Autodesk Fusion 360 part; units mm, degrees
(part 25 of 28)
  line L2372 (136.268, 61.3167, -1.4859) -> (136.2719, 61.4148, -1.4859)
  line L2373 (136.2719, 61.4148, -1.4859) -> (136.3026, 61.6085, -1.4859)
  line L2374 (136.3026, 61.6085, -1.4859) -> (136.3632, 61.7951, -1.4859)
  line L2375 (136.3632, 61.7951, -1.4859) -> (136.4522, 61.9699, -1.4859)
  line L2376 (136.4522, 61.9699, -1.4859) -> (136.5675, 62.1286, -1.4859)
  line L2377 (136.5675, 62.1286, -1.4859) -> (136.7062, 62.2672, -1.4859)
  line L2378 (136.7062, 62.2672, -1.4859) -> (136.8649, 62.3825, -1.4859)
  line L2379 (136.8649, 62.3825, -1.4859) -> (137.0397, 62.4716, -1.4859)
  line L2380 (137.0397, 62.4716, -1.4859) -> (137.2262, 62.5322, -1.4859)
  line L2381 (137.2262, 62.5322, -1.4859) -> (137.42, 62.5629, -1.4859)
  line L2382 (137.42, 62.5629, -1.4859) -> (137.6161, 62.5629, -1.4859)
  line L2383 (137.6161, 62.5629, -1.4859) -> (137.8099, 62.5322, -1.4859)
  line L2384 (16.561, 65.3929, -1.4859) -> (16.7547, 65.3622, -1.4859)
  line L2385 (16.7547, 65.3622, -1.4859) -> (16.9412, 65.3016, -1.4859)
  line L2386 (16.9412, 65.3016, -1.4859) -> (17.116, 65.2126, -1.4859)
  line L2387 (17.116, 65.2126, -1.4859) -> (17.2747, 65.0973, -1.4859)
  line L2388 (17.2747, 65.0973, -1.4859) -> (17.4134, 64.9586, -1.4859)
  line L2389 (17.4134, 64.9586, -1.4859) -> (17.5287, 64.7999, -1.4859)
  line L2390 (17.5287, 64.7999, -1.4859) -> (17.6177, 64.6251, -1.4859)
  line L2391 (17.6177, 64.6251, -1.4859) -> (17.6784, 64.4386, -1.4859)
  line L2392 (17.6784, 64.4386, -1.4859) -> (17.709, 64.2448, -1.4859)
  line L2393 (17.709, 64.2448, -1.4859) -> (17.709, 64.0487, -1.4859)
  line L2394 (17.709, 64.0487, -1.4859) -> (17.6784, 63.855, -1.4859)
  line L2395 (17.6784, 63.855, -1.4859) -> (17.6177, 63.6684, -1.4859)
  line L2396 (17.6177, 63.6684, -1.4859) -> (17.5287, 63.4936, -1.4859)
  line L2397 (17.5287, 63.4936, -1.4859) -> (17.4134, 63.335, -1.4859)
  line L2398 (17.4134, 63.335, -1.4859) -> (17.2747, 63.1963, -1.4859)
  line L2399 (17.2747, 63.1963, -1.4859) -> (17.116, 63.081, -1.4859)
  line L2400 (17.116, 63.081, -1.4859) -> (16.9412, 62.9919, -1.4859)
  line L2401 (16.9412, 62.9919, -1.4859) -> (16.7547, 62.9313, -1.4859)
  line L2402 (16.7547, 62.9313, -1.4859) -> (16.561, 62.9006, -1.4859)
  line L2403 (16.561, 62.9006, -1.4859) -> (16.4629, 62.8968, -1.4859)
  line L2404 (16.4629, 62.8968, -1.4859) -> (15.9629, 62.8968, -1.4859)
  line L2405 (15.9629, 62.8968, -1.4859) -> (15.8648, 62.9006, -1.4859)
  line L2406 (15.8648, 62.9006, -1.4859) -> (15.6711, 62.9313, -1.4859)
  line L2407 (15.6711, 62.9313, -1.4859) -> (15.4845, 62.9919, -1.4859)
  line L2408 (15.4845, 62.9919, -1.4859) -> (15.3098, 63.081, -1.4859)
  line L2409 (15.3098, 63.081, -1.4859) -> (15.1511, 63.1963, -1.4859)
  line L2410 (15.1511, 63.1963, -1.4859) -> (15.0124, 63.335, -1.4859)
  line L2411 (15.0124, 63.335, -1.4859) -> (14.8971, 63.4936, -1.4859)
  line L2412 (14.8971, 63.4936, -1.4859) -> (14.808, 63.6684, -1.4859)
  line L2413 (14.808, 63.6684, -1.4859) -> (14.7474, 63.855, -1.4859)
  line L2414 (14.7474, 63.855, -1.4859) -> (14.7167, 64.0487, -1.4859)
  line L2415 (14.7167, 64.0487, -1.4859) -> (14.7167, 64.2448, -1.4859)
  line L2416 (14.7167, 64.2448, -1.4859) -> (14.7474, 64.4386, -1.4859)
  line L2417 (14.7474, 64.4386, -1.4859) -> (14.808, 64.6251, -1.4859)
  line L2418 (14.808, 64.6251, -1.4859) -> (14.8971, 64.7999, -1.4859)
  line L2419 (14.8971, 64.7999, -1.4859) -> (15.0124, 64.9586, -1.4859)
  line L2420 (15.0124, 64.9586, -1.4859) -> (15.1511, 65.0973, -1.4859)
  line L2421 (15.1511, 65.0973, -1.4859) -> (15.3098, 65.2126, -1.4859)
  line L2422 (15.3098, 65.2126, -1.4859) -> (15.4845, 65.3016, -1.4859)
  line L2423 (15.4845, 65.3016, -1.4859) -> (15.6711, 65.3622, -1.4859)
  line L2424 (15.6711, 65.3622, -1.4859) -> (15.8648, 65.3929, -1.4859)
  line L2425 (15.8648, 65.3929, -1.4859) -> (15.9629, 65.3968, -1.4859)
  line L2426 (15.9629, 65.3968, -1.4859) -> (16.4629, 65.3968, -1.4859)
  line L2427 (16.4629, 65.3968, -1.4859) -> (16.561, 65.3929, -1.4859)
  line L2428 (24.181, 65.3929, -1.4859) -> (24.3747, 65.3622, -1.4859)
  line L2429 (24.3747, 65.3622, -1.4859) -> (24.5612, 65.3016, -1.4859)
  line L2430 (24.5612, 65.3016, -1.4859) -> (24.736, 65.2126, -1.4859)
  line L2431 (24.736, 65.2126, -1.4859) -> (24.8947, 65.0973, -1.4859)
  line L2432 (24.8947, 65.0973, -1.4859) -> (25.0334, 64.9586, -1.4859)
  line L2433 (25.0334, 64.9586, -1.4859) -> (25.1487, 64.7999, -1.4859)
  line L2434 (25.1487, 64.7999, -1.4859) -> (25.2377, 64.6251, -1.4859)
  line L2435 (25.2377, 64.6251, -1.4859) -> (25.2983, 64.4386, -1.4859)
  line L2436 (25.2984, 64.4386, -1.4859) -> (25.329, 64.2448, -1.4859)
  line L2437 (25.329, 64.2448, -1.4859) -> (25.329, 64.0487, -1.4859)
  line L2438 (25.329, 64.0487, -1.4859) -> (25.2984, 63.855, -1.4859)
  line L2439 (25.2984, 63.855, -1.4859) -> (25.2377, 63.6684, -1.4859)
  line L2440 (25.2377, 63.6684, -1.4859) -> (25.1487, 63.4936, -1.4859)
  line L2441 (25.1487, 63.4936, -1.4859) -> (25.0334, 63.335, -1.4859)
  line L2442 (25.0334, 63.335, -1.4859) -> (24.8947, 63.1963, -1.4859)
  line L2443 (24.8947, 63.1963, -1.4859) -> (24.736, 63.081, -1.4859)
  line L2444 (24.736, 63.081, -1.4859) -> (24.5612, 62.9919, -1.4859)
  line L2445 (24.5612, 62.9919, -1.4859) -> (24.3747, 62.9313, -1.4859)
  line L2446 (24.3747, 62.9313, -1.4859) -> (24.181, 62.9006, -1.4859)
  line L2447 (24.181, 62.9006, -1.4859) -> (24.0829, 62.8968, -1.4859)
  line L2448 (24.0829, 62.8968, -1.4859) -> (23.5829, 62.8968, -1.4859)
  line L2449 (23.5829, 62.8968, -1.4859) -> (23.4848, 62.9006, -1.4859)
  line L2450 (23.4848, 62.9006, -1.4859) -> (23.2911, 62.9313, -1.4859)
  line L2451 (23.2911, 62.9313, -1.4859) -> (23.1045, 62.9919, -1.4859)
  line L2452 (23.1045, 62.9919, -1.4859) -> (22.9298, 63.081, -1.4859)
  line L2453 (22.9298, 63.081, -1.4859) -> (22.7711, 63.1963, -1.4859)
  line L2454 (22.7711, 63.1963, -1.4859) -> (22.6324, 63.335, -1.4859)
  line L2455 (22.6324, 63.335, -1.4859) -> (22.5171, 63.4936, -1.4859)
  line L2456 (22.5171, 63.4936, -1.4859) -> (22.428, 63.6684, -1.4859)
  line L2457 (22.428, 63.6684, -1.4859) -> (22.3674, 63.855, -1.4859)
  line L2458 (22.3674, 63.855, -1.4859) -> (22.3367, 64.0487, -1.4859)
  line L2459 (22.3367, 64.0487, -1.4859) -> (22.3367, 64.2448, -1.4859)
  line L2460 (22.3367, 64.2448, -1.4859) -> (22.3674, 64.4386, -1.4859)
  line L2461 (22.3674, 64.4386, -1.4859) -> (22.428, 64.6251, -1.4859)
  line L2462 (22.428, 64.6251, -1.4859) -> (22.5171, 64.7999, -1.4859)
  line L2463 (22.5171, 64.7999, -1.4859) -> (22.6324, 64.9586, -1.4859)
  line L2464 (22.6324, 64.9586, -1.4859) -> (22.7711, 65.0973, -1.4859)
  line L2465 (22.7711, 65.0973, -1.4859) -> (22.9298, 65.2126, -1.4859)
  line L2466 (22.9298, 65.2126, -1.4859) -> (23.1045, 65.3016, -1.4859)
  line L2467 (23.1045, 65.3016, -1.4859) -> (23.2911, 65.3622, -1.4859)
  line L2468 (23.2911, 65.3622, -1.4859) -> (23.4848, 65.3929, -1.4859)
  line L2469 (23.4848, 65.3929, -1.4859) -> (23.5829, 65.3968, -1.4859)
  line L2470 (23.5829, 65.3968, -1.4859) -> (24.0829, 65.3968, -1.4859)
  line L2471 (24.0829, 65.3968, -1.4859) -> (24.181, 65.3929, -1.4859)
  line L2472 (51.486, 65.3929, -1.4859) -> (51.6797, 65.3622, -1.4859)
  line L2473 (51.6797, 65.3622, -1.4859) -> (51.8662, 65.3016, -1.4859)
  line L2474 (51.8662, 65.3016, -1.4859) -> (52.041, 65.2126, -1.4859)
  line L2475 (52.041, 65.2126, -1.4859) -> (52.1997, 65.0973, -1.4859)
  line L2476 (52.1997, 65.0973, -1.4859) -> (52.3384, 64.9586, -1.4859)
  line L2477 (52.3384, 64.9586, -1.4859) -> (52.4537, 64.7999, -1.4859)
  line L2478 (52.4537, 64.7999, -1.4859) -> (52.5427, 64.6251, -1.4859)
  line L2479 (52.5427, 64.6251, -1.4859) -> (52.6033, 64.4386, -1.4859)
  line L2480 (52.6033, 64.4386, -1.4859) -> (52.634, 64.2448, -1.4859)
  line L2481 (52.634, 64.2448, -1.4859) -> (52.634, 64.0487, -1.4859)
  line L2482 (52.634, 64.0487, -1.4859) -> (52.6033, 63.855, -1.4859)
  line L2483 (52.6033, 63.855, -1.4859) -> (52.5427, 63.6684, -1.4859)
  line L2484 (52.5427, 63.6684, -1.4859) -> (52.4537, 63.4936, -1.4859)
  line L2485 (52.4537, 63.4936, -1.4859) -> (52.3384, 63.335, -1.4859)
  line L2486 (52.3384, 63.335, -1.4859) -> (52.1997, 63.1963, -1.4859)
  line L2487 (52.1997, 63.1963, -1.4859) -> (52.041, 63.081, -1.4859)
  line L2488 (52.041, 63.081, -1.4859) -> (51.8662, 62.9919, -1.4859)
  line L2489 (51.8662, 62.9919, -1.4859) -> (51.6797, 62.9313, -1.4859)
  line L2490 (51.6797, 62.9313, -1.4859) -> (51.486, 62.9006, -1.4859)
  line L2491 (51.486, 62.9006, -1.4859) -> (51.3879, 62.8968, -1.4859)
  line L2492 (51.3879, 62.8968, -1.4859) -> (50.8879, 62.8968, -1.4859)
  line L2493 (50.8879, 62.8968, -1.4859) -> (50.7898, 62.9006, -1.4859)
  line L2494 (50.7898, 62.9006, -1.4859) -> (50.5961, 62.9313, -1.4859)
  line L2495 (50.5961, 62.9313, -1.4859) -> (50.4095, 62.9919, -1.4859)
  line L2496 (50.4095, 62.9919, -1.4859) -> (50.2348, 63.081, -1.4859)
  line L2497 (50.2348, 63.081, -1.4859) -> (50.0761, 63.1963, -1.4859)
  line L2498 (50.0761, 63.1963, -1.4859) -> (49.9374, 63.335, -1.4859)
  line L2499 (49.9374, 63.335, -1.4859) -> (49.8221, 63.4936, -1.4859)
  line L2500 (49.8221, 63.4936, -1.4859) -> (49.733, 63.6684, -1.4859)
  line L2501 (49.733, 63.6684, -1.4859) -> (49.6724, 63.855, -1.4859)
  line L2502 (49.6724, 63.855, -1.4859) -> (49.6417, 64.0487, -1.4859)
  line L2503 (49.6417, 64.0487, -1.4859) -> (49.6417, 64.2448, -1.4859)
  line L2504 (49.6417, 64.2448, -1.4859) -> (49.6724, 64.4386, -1.4859)
  line L2505 (49.6724, 64.4386, -1.4859) -> (49.733, 64.6251, -1.4859)
  line L2506 (49.733, 64.6251, -1.4859) -> (49.8221, 64.7999, -1.4859)
  line L2507 (49.8221, 64.7999, -1.4859) -> (49.9374, 64.9586, -1.4859)
  line L2508 (49.9374, 64.9586, -1.4859) -> (50.0761, 65.0973, -1.4859)
  line L2509 (50.0761, 65.0973, -1.4859) -> (50.2348, 65.2126, -1.4859)
  line L2510 (50.2348, 65.2126, -1.4859) -> (50.4095, 65.3016, -1.4859)
  line L2511 (50.4095, 65.3016, -1.4859) -> (50.5961, 65.3622, -1.4859)
  line L2512 (50.5961, 65.3622, -1.4859) -> (50.7898, 65.3929, -1.4859)
  line L2513 (50.7898, 65.3929, -1.4859) -> (50.8879, 65.3968, -1.4859)
  line L2514 (50.8879, 65.3968, -1.4859) -> (51.3879, 65.3968, -1.4859)
  line L2515 (51.3879, 65.3968, -1.4859) -> (51.486, 65.3929, -1.4859)
  line L2516 (59.106, 65.3929, -1.4859) -> (59.2997, 65.3622, -1.4859)
  line L2517 (59.2997, 65.3622, -1.4859) -> (59.4862, 65.3016, -1.4859)
  line L2518 (59.4862, 65.3016, -1.4859) -> (59.661, 65.2126, -1.4859)
  line L2519 (59.661, 65.2126, -1.4859) -> (59.8197, 65.0973, -1.4859)
  line L2520 (59.8197, 65.0973, -1.4859) -> (59.9584, 64.9586, -1.4859)
  line L2521 (59.9584, 64.9586, -1.4859) -> (60.0737, 64.7999, -1.4859)
  line L2522 (60.0737, 64.7999, -1.4859) -> (60.1627, 64.6251, -1.4859)
  line L2523 (60.1627, 64.6251, -1.4859) -> (60.2234, 64.4386, -1.4859)
  line L2524 (60.2234, 64.4386, -1.4859) -> (60.254, 64.2448, -1.4859)
  line L2525 (60.254, 64.2448, -1.4859) -> (60.254, 64.0487, -1.4859)
  line L2526 (60.254, 64.0487, -1.4859) -> (60.2233, 63.855, -1.4859)
  line L2527 (60.2233, 63.855, -1.4859) -> (60.1627, 63.6684, -1.4859)
  line L2528 (60.1627, 63.6684, -1.4859) -> (60.0737, 63.4936, -1.4859)
  line L2529 (60.0737, 63.4936, -1.4859) -> (59.9584, 63.335, -1.4859)
  line L2530 (59.9584, 63.335, -1.4859) -> (59.8197, 63.1963, -1.4859)
  line L2531 (59.8197, 63.1963, -1.4859) -> (59.661, 63.081, -1.4859)
  line L2532 (59.661, 63.081, -1.4859) -> (59.4862, 62.9919, -1.4859)
  line L2533 (59.4862, 62.9919, -1.4859) -> (59.2997, 62.9313, -1.4859)
  line L2534 (59.2997, 62.9313, -1.4859) -> (59.106, 62.9006, -1.4859)
  line L2535 (59.106, 62.9006, -1.4859) -> (59.0079, 62.8968, -1.4859)
  line L2536 (59.0079, 62.8968, -1.4859) -> (58.5079, 62.8968, -1.4859)
  line L2537 (58.5079, 62.8968, -1.4859) -> (58.4098, 62.9006, -1.4859)
  line L2538 (58.4098, 62.9006, -1.4859) -> (58.2161, 62.9313, -1.4859)
  line L2539 (58.2161, 62.9313, -1.4859) -> (58.0295, 62.9919, -1.4859)
  line L2540 (58.0295, 62.9919, -1.4859) -> (57.8548, 63.081, -1.4859)
  line L2541 (57.8548, 63.081, -1.4859) -> (57.6961, 63.1963, -1.4859)
  line L2542 (57.6961, 63.1963, -1.4859) -> (57.5574, 63.335, -1.4859)
  line L2543 (57.5574, 63.335, -1.4859) -> (57.4421, 63.4936, -1.4859)
  line L2544 (57.4421, 63.4936, -1.4859) -> (57.353, 63.6684, -1.4859)
  line L2545 (57.353, 63.6684, -1.4859) -> (57.2924, 63.855, -1.4859)
  line L2546 (57.2924, 63.855, -1.4859) -> (57.2617, 64.0487, -1.4859)
  line L2547 (57.2617, 64.0487, -1.4859) -> (57.2617, 64.2448, -1.4859)
  line L2548 (57.2617, 64.2448, -1.4859) -> (57.2924, 64.4386, -1.4859)
  line L2549 (57.2924, 64.4386, -1.4859) -> (57.353, 64.6251, -1.4859)
  line L2550 (57.353, 64.6251, -1.4859) -> (57.4421, 64.7999, -1.4859)
  line L2551 (57.4421, 64.7999, -1.4859) -> (57.5574, 64.9586, -1.4859)
  line L2552 (57.5574, 64.9586, -1.4859) -> (57.6961, 65.0973, -1.4859)
  line L2553 (57.6961, 65.0973, -1.4859) -> (57.8548, 65.2126, -1.4859)
  line L2554 (57.8548, 65.2126, -1.4859) -> (58.0295, 65.3016, -1.4859)
  line L2555 (58.0295, 65.3016, -1.4859) -> (58.2161, 65.3622, -1.4859)
  line L2556 (58.2161, 65.3622, -1.4859) -> (58.4098, 65.3929, -1.4859)
  line L2557 (58.4098, 65.3929, -1.4859) -> (58.5079, 65.3968, -1.4859)
  line L2558 (58.5079, 65.3968, -1.4859) -> (59.0079, 65.3968, -1.4859)
  line L2559 (59.0079, 65.3968, -1.4859) -> (59.106, 65.3929, -1.4859)
  line L2560 (86.411, 65.3929, -1.4859) -> (86.6047, 65.3622, -1.4859)
  line L2561 (86.6047, 65.3622, -1.4859) -> (86.7912, 65.3016, -1.4859)
  line L2562 (86.7912, 65.3016, -1.4859) -> (86.966, 65.2126, -1.4859)
  line L2563 (86.966, 65.2126, -1.4859) -> (87.1247, 65.0973, -1.4859)
  line L2564 (87.1247, 65.0973, -1.4859) -> (87.2634, 64.9586, -1.4859)
  line L2565 (87.2634, 64.9586, -1.4859) -> (87.3787, 64.7999, -1.4859)
  line L2566 (87.3787, 64.7999, -1.4859) -> (87.4677, 64.6251, -1.4859)
  line L2567 (87.4677, 64.6251, -1.4859) -> (87.5284, 64.4386, -1.4859)
  line L2568 (87.5284, 64.4386, -1.4859) -> (87.559, 64.2448, -1.4859)
  line L2569 (87.559, 64.2448, -1.4859) -> (87.559, 64.0487, -1.4859)
  line L2570 (87.559, 64.0487, -1.4859) -> (87.5283, 63.855, -1.4859)
  line L2571 (87.5283, 63.855, -1.4859) -> (87.4677, 63.6684, -1.4859)
  line L2572 (87.4677, 63.6684, -1.4859) -> (87.3787, 63.4936, -1.4859)
  line L2573 (87.3787, 63.4936, -1.4859) -> (87.2634, 63.335, -1.4859)
  line L2574 (87.2634, 63.335, -1.4859) -> (87.1247, 63.1963, -1.4859)
  line L2575 (87.1247, 63.1963, -1.4859) -> (86.966, 63.081, -1.4859)
  line L2576 (86.966, 63.081, -1.4859) -> (86.7912, 62.9919, -1.4859)
  line L2577 (86.7912, 62.9919, -1.4859) -> (86.6047, 62.9313, -1.4859)
  line L2578 (86.6047, 62.9313, -1.4859) -> (86.411, 62.9006, -1.4859)
  line L2579 (86.411, 62.9006, -1.4859) -> (86.3129, 62.8968, -1.4859)
  line L2580 (86.3129, 62.8968, -1.4859) -> (85.8129, 62.8968, -1.4859)
  line L2581 (85.8129, 62.8968, -1.4859) -> (85.7148, 62.9006, -1.4859)
  line L2582 (85.7148, 62.9006, -1.4859) -> (85.5211, 62.9313, -1.4859)
  line L2583 (85.5211, 62.9313, -1.4859) -> (85.3345, 62.9919, -1.4859)
  line L2584 (85.3345, 62.9919, -1.4859) -> (85.1598, 63.081, -1.4859)
  line L2585 (85.1598, 63.081, -1.4859) -> (85.0011, 63.1963, -1.4859)
  line L2586 (85.0011, 63.1963, -1.4859) -> (84.8624, 63.335, -1.4859)
  line L2587 (84.8624, 63.335, -1.4859) -> (84.7471, 63.4936, -1.4859)
  line L2588 (84.7471, 63.4936, -1.4859) -> (84.658, 63.6684, -1.4859)
  line L2589 (84.658, 63.6684, -1.4859) -> (84.5974, 63.855, -1.4859)
  line L2590 (84.5974, 63.855, -1.4859) -> (84.5667, 64.0487, -1.4859)
  line L2591 (84.5667, 64.0487, -1.4859) -> (84.5667, 64.2448, -1.4859)
  line L2592 (84.5667, 64.2448, -1.4859) -> (84.5974, 64.4386, -1.4859)
  line L2593 (84.5974, 64.4386, -1.4859) -> (84.658, 64.6251, -1.4859)
  line L2594 (84.658, 64.6251, -1.4859) -> (84.7471, 64.7999, -1.4859)
  line L2595 (84.7471, 64.7999, -1.4859) -> (84.8624, 64.9586, -1.4859)
  line L2596 (84.8624, 64.9586, -1.4859) -> (85.0011, 65.0973, -1.4859)
  line L2597 (85.0011, 65.0973, -1.4859) -> (85.1598, 65.2126, -1.4859)
  line L2598 (85.1598, 65.2126, -1.4859) -> (85.3345, 65.3016, -1.4859)
  line L2599 (85.3345, 65.3016, -1.4859) -> (85.5211, 65.3622, -1.4859)
  line L2600 (85.5211, 65.3622, -1.4859) -> (85.7148, 65.3929, -1.4859)
  line L2601 (85.7148, 65.3929, -1.4859) -> (85.8129, 65.3968, -1.4859)
  line L2602 (85.8129, 65.3968, -1.4859) -> (86.3129, 65.3968, -1.4859)
  line L2603 (86.3129, 65.3968, -1.4859) -> (86.411, 65.3929, -1.4859)
  line L2604 (94.031, 65.3929, -1.4859) -> (94.2247, 65.3622, -1.4859)
  line L2605 (94.2247, 65.3622, -1.4859) -> (94.4112, 65.3016, -1.4859)
  line L2606 (94.4112, 65.3016, -1.4859) -> (94.586, 65.2126, -1.4859)
  line L2607 (94.586, 65.2126, -1.4859) -> (94.7447, 65.0973, -1.4859)
  line L2608 (94.7447, 65.0973, -1.4859) -> (94.8834, 64.9586, -1.4859)
  line L2609 (94.8834, 64.9586, -1.4859) -> (94.9987, 64.7999, -1.4859)
  line L2610 (94.9987, 64.7999, -1.4859) -> (95.0877, 64.6251, -1.4859)
  line L2611 (95.0877, 64.6251, -1.4859) -> (95.1483, 64.4386, -1.4859)
  line L2612 (95.1483, 64.4386, -1.4859) -> (95.179, 64.2448, -1.4859)
  line L2613 (95.179, 64.2448, -1.4859) -> (95.179, 64.0487, -1.4859)
  line L2614 (95.179, 64.0487, -1.4859) -> (95.1483, 63.855, -1.4859)
  line L2615 (95.1483, 63.855, -1.4859) -> (95.0877, 63.6684, -1.4859)
  line L2616 (95.0877, 63.6684, -1.4859) -> (94.9987, 63.4936, -1.4859)
  line L2617 (94.9987, 63.4936, -1.4859) -> (94.8834, 63.335, -1.4859)
  line L2618 (94.8834, 63.335, -1.4859) -> (94.7447, 63.1963, -1.4859)
  line L2619 (94.7447, 63.1963, -1.4859) -> (94.586, 63.081, -1.4859)
  line L2620 (94.586, 63.081, -1.4859) -> (94.4112, 62.9919, -1.4859)
  line L2621 (94.4112, 62.9919, -1.4859) -> (94.2247, 62.9313, -1.4859)
  line L2622 (94.2247, 62.9313, -1.4859) -> (94.031, 62.9006, -1.4859)
  line L2623 (94.031, 62.9006, -1.4859) -> (93.9329, 62.8968, -1.4859)
  line L2624 (93.9329, 62.8968, -1.4859) -> (93.4329, 62.8968, -1.4859)
  line L2625 (93.4329, 62.8968, -1.4859) -> (93.3348, 62.9006, -1.4859)
  line L2626 (93.3348, 62.9006, -1.4859) -> (93.1411, 62.9313, -1.4859)
  line L2627 (93.1411, 62.9313, -1.4859) -> (92.9545, 62.9919, -1.4859)
  line L2628 (92.9545, 62.9919, -1.4859) -> (92.7798, 63.081, -1.4859)
  line L2629 (92.7798, 63.081, -1.4859) -> (92.6211, 63.1963, -1.4859)
  line L2630 (92.6211, 63.1963, -1.4859) -> (92.4824, 63.335, -1.4859)
  line L2631 (92.4824, 63.335, -1.4859) -> (92.3671, 63.4936, -1.4859)
  line L2632 (92.3671, 63.4936, -1.4859) -> (92.278, 63.6684, -1.4859)
  line L2633 (92.278, 63.6684, -1.4859) -> (92.2174, 63.855, -1.4859)
  line L2634 (92.2174, 63.855, -1.4859) -> (92.1867, 64.0487, -1.4859)
  line L2635 (92.1867, 64.0487, -1.4859) -> (92.1867, 64.2448, -1.4859)
  line L2636 (92.1867, 64.2448, -1.4859) -> (92.2174, 64.4386, -1.4859)
  line L2637 (92.2174, 64.4386, -1.4859) -> (92.278, 64.6251, -1.4859)
  line L2638 (92.278, 64.6251, -1.4859) -> (92.3671, 64.7999, -1.4859)
  line L2639 (92.3671, 64.7999, -1.4859) -> (92.4824, 64.9586, -1.4859)
  line L2640 (92.4824, 64.9586, -1.4859) -> (92.6211, 65.0973, -1.4859)
  line L2641 (92.6211, 65.0973, -1.4859) -> (92.7798, 65.2126, -1.4859)
  line L2642 (92.7798, 65.2126, -1.4859) -> (92.9545, 65.3016, -1.4859)
  line L2643 (92.9545, 65.3016, -1.4859) -> (93.1411, 65.3622, -1.4859)
  line L2644 (93.1411, 65.3622, -1.4859) -> (93.3348, 65.3929, -1.4859)
  line L2645 (93.3348, 65.3929, -1.4859) -> (93.4329, 65.3968, -1.4859)
  line L2646 (93.4329, 65.3968, -1.4859) -> (93.9329, 65.3968, -1.4859)
  line L2647 (93.9329, 65.3968, -1.4859) -> (94.031, 65.3929, -1.4859)
  line L2648 (121.336, 65.3929, -1.4859) -> (121.5297, 65.3622, -1.4859)
  line L2649 (121.5297, 65.3622, -1.4859) -> (121.7162, 65.3016, -1.4859)
  line L2650 (121.7162, 65.3016, -1.4859) -> (121.891, 65.2126, -1.4859)
  line L2651 (121.891, 65.2126, -1.4859) -> (122.0497, 65.0973, -1.4859)
  line L2652 (122.0497, 65.0973, -1.4859) -> (122.1884, 64.9586, -1.4859)
  line L2653 (122.1884, 64.9586, -1.4859) -> (122.3037, 64.7999, -1.4859)
  line L2654 (122.3037, 64.7999, -1.4859) -> (122.3927, 64.6251, -1.4859)
  line L2655 (122.3927, 64.6251, -1.4859) -> (122.4533, 64.4386, -1.4859)
  line L2656 (122.4533, 64.4386, -1.4859) -> (122.484, 64.2448, -1.4859)
  line L2657 (122.484, 64.2448, -1.4859) -> (122.484, 64.0487, -1.4859)
  line L2658 (122.484, 64.0487, -1.4859) -> (122.4534, 63.855, -1.4859)
  line L2659 (122.4533, 63.855, -1.4859) -> (122.3927, 63.6684, -1.4859)
  line L2660 (122.3927, 63.6684, -1.4859) -> (122.3037, 63.4936, -1.4859)
  line L2661 (122.3037, 63.4936, -1.4859) -> (122.1884, 63.335, -1.4859)
  line L2662 (122.1884, 63.335, -1.4859) -> (122.0497, 63.1963, -1.4859)
  line L2663 (122.0497, 63.1963, -1.4859) -> (121.891, 63.081, -1.4859)
  line L2664 (121.891, 63.081, -1.4859) -> (121.7162, 62.9919, -1.4859)
  line L2665 (121.7162, 62.9919, -1.4859) -> (121.5297, 62.9313, -1.4859)
  line L2666 (121.5297, 62.9313, -1.4859) -> (121.336, 62.9006, -1.4859)
  line L2667 (121.336, 62.9006, -1.4859) -> (121.2379, 62.8968, -1.4859)
  line L2668 (121.2379, 62.8968, -1.4859) -> (120.7379, 62.8968, -1.4859)
  line L2669 (120.7379, 62.8968, -1.4859) -> (120.6398, 62.9006, -1.4859)
  line L2670 (120.6398, 62.9006, -1.4859) -> (120.4461, 62.9313, -1.4859)
  line L2671 (120.4461, 62.9313, -1.4859) -> (120.2595, 62.9919, -1.4859)
  line L2672 (120.2595, 62.9919, -1.4859) -> (120.0848, 63.081, -1.4859)
  line L2673 (120.0848, 63.081, -1.4859) -> (119.9261, 63.1963, -1.4859)
  line L2674 (119.9261, 63.1963, -1.4859) -> (119.7874, 63.335, -1.4859)
  line L2675 (119.7874, 63.335, -1.4859) -> (119.6721, 63.4936, -1.4859)
  line L2676 (119.6721, 63.4936, -1.4859) -> (119.583, 63.6684, -1.4859)
  line L2677 (119.583, 63.6684, -1.4859) -> (119.5224, 63.855, -1.4859)
  line L2678 (119.5224, 63.855, -1.4859) -> (119.4917, 64.0487, -1.4859)
  line L2679 (119.4917, 64.0487, -1.4859) -> (119.4917, 64.2448, -1.4859)
  line L2680 (119.4917, 64.2448, -1.4859) -> (119.5224, 64.4386, -1.4859)
  line L2681 (119.5224, 64.4386, -1.4859) -> (119.583, 64.6251, -1.4859)
  line L2682 (119.583, 64.6251, -1.4859) -> (119.6721, 64.7999, -1.4859)
  line L2683 (119.6721, 64.7999, -1.4859) -> (119.7874, 64.9586, -1.4859)
  line L2684 (119.7874, 64.9586, -1.4859) -> (119.9261, 65.0973, -1.4859)
  line L2685 (119.9261, 65.0973, -1.4859) -> (120.0848, 65.2126, -1.4859)
  line L2686 (120.0848, 65.2126, -1.4859) -> (120.2595, 65.3016, -1.4859)
  line L2687 (120.2595, 65.3016, -1.4859) -> (120.4461, 65.3622, -1.4859)
  line L2688 (120.4461, 65.3622, -1.4859) -> (120.6398, 65.3929, -1.4859)
  line L2689 (120.6398, 65.3929, -1.4859) -> (120.7379, 65.3968, -1.4859)
  line L2690 (120.7379, 65.3968, -1.4859) -> (121.2379, 65.3968, -1.4859)
  line L2691 (121.2379, 65.3968, -1.4859) -> (121.336, 65.3929, -1.4859)
  line L2692 (128.956, 65.3929, -1.4859) -> (129.1497, 65.3622, -1.4859)
  line L2693 (129.1497, 65.3622, -1.4859) -> (129.3362, 65.3016, -1.4859)
  line L2694 (129.3362, 65.3016, -1.4859) -> (129.511, 65.2126, -1.4859)
  line L2695 (129.511, 65.2126, -1.4859) -> (129.6697, 65.0973, -1.4859)
  line L2696 (129.6697, 65.0973, -1.4859) -> (129.8084, 64.9586, -1.4859)
  line L2697 (129.8084, 64.9586, -1.4859) -> (129.9237, 64.7999, -1.4859)
  line L2698 (129.9237, 64.7999, -1.4859) -> (130.0127, 64.6251, -1.4859)
  line L2699 (130.0127, 64.6251, -1.4859) -> (130.0733, 64.4386, -1.4859)
  line L2700 (130.0733, 64.4386, -1.4859) -> (130.104, 64.2448, -1.4859)
  line L2701 (130.104, 64.2448, -1.4859) -> (130.104, 64.0487, -1.4859)
  line L2702 (130.104, 64.0487, -1.4859) -> (130.0734, 63.855, -1.4859)
  line L2703 (130.0734, 63.855, -1.4859) -> (130.0127, 63.6684, -1.4859)
  line L2704 (130.0127, 63.6684, -1.4859) -> (129.9237, 63.4936, -1.4859)
  line L2705 (129.9237, 63.4936, -1.4859) -> (129.8084, 63.335, -1.4859)
  line L2706 (129.8084, 63.335, -1.4859) -> (129.6697, 63.1963, -1.4859)
  line L2707 (129.6697, 63.1963, -1.4859) -> (129.511, 63.081, -1.4859)
  line L2708 (129.511, 63.081, -1.4859) -> (129.3362, 62.9919, -1.4859)
  line L2709 (129.3362, 62.9919, -1.4859) -> (129.1497, 62.9313, -1.4859)
  line L2710 (129.1497, 62.9313, -1.4859) -> (128.956, 62.9006, -1.4859)
  line L2711 (128.956, 62.9006, -1.4859) -> (128.8579, 62.8968, -1.4859)
  line L2712 (128.8579, 62.8968, -1.4859) -> (128.3579, 62.8968, -1.4859)
  line L2713 (128.3579, 62.8968, -1.4859) -> (128.2598, 62.9006, -1.4859)
  line L2714 (128.2598, 62.9006, -1.4859) -> (128.0661, 62.9313, -1.4859)
  line L2715 (128.0661, 62.9313, -1.4859) -> (127.8795, 62.9919, -1.4859)
  line L2716 (127.8795, 62.9919, -1.4859) -> (127.7048, 63.081, -1.4859)
  line L2717 (127.7048, 63.081, -1.4859) -> (127.5461, 63.1963, -1.4859)
  line L2718 (127.5461, 63.1963, -1.4859) -> (127.4074, 63.335, -1.4859)
  line L2719 (127.4074, 63.335, -1.4859) -> (127.2921, 63.4936, -1.4859)
  line L2720 (127.2921, 63.4936, -1.4859) -> (127.203, 63.6684, -1.4859)
  line L2721 (127.203, 63.6684, -1.4859) -> (127.1424, 63.855, -1.4859)
  line L2722 (127.1424, 63.855, -1.4859) -> (127.1117, 64.0487, -1.4859)
  line L2723 (127.1117, 64.0487, -1.4859) -> (127.1117, 64.2448, -1.4859)
  line L2724 (127.1117, 64.2448, -1.4859) -> (127.1424, 64.4386, -1.4859)
  line L2725 (127.1424, 64.4386, -1.4859) -> (127.203, 64.6251, -1.4859)
  line L2726 (127.203, 64.6251, -1.4859) -> (127.2921, 64.7999, -1.4859)
  line L2727 (127.2921, 64.7999, -1.4859) -> (127.4074, 64.9586, -1.4859)
  line L2728 (127.4074, 64.9586, -1.4859) -> (127.5461, 65.0973, -1.4859)
  line L2729 (127.5461, 65.0973, -1.4859) -> (127.7048, 65.2126, -1.4859)
  line L2730 (127.7048, 65.2126, -1.4859) -> (127.8795, 65.3016, -1.4859)
  line L2731 (127.8795, 65.3016, -1.4859) -> (128.0661, 65.3622, -1.4859)
  line L2732 (128.0661, 65.3622, -1.4859) -> (128.2598, 65.3929, -1.4859)
  line L2733 (128.2598, 65.3929, -1.4859) -> (128.3579, 65.3968, -1.4859)
  line L2734 (128.3579, 65.3968, -1.4859) -> (128.8579, 65.3968, -1.4859)
  line L2735 (128.8579, 65.3968, -1.4859) -> (128.956, 65.3929, -1.4859)
  line L2736 (33.0348, 70.1522, -1.4859) -> (33.2214, 70.0916, -1.4859)
  line L2737 (33.2214, 70.0916, -1.4859) -> (33.3962, 70.0025, -1.4859)
  line L2738 (33.3962, 70.0025, -1.4859) -> (33.5549, 69.8872, -1.4859)
  line L2739 (33.5549, 69.8872, -1.4859) -> (33.6936, 69.7485, -1.4859)
  line L2740 (33.6936, 69.7485, -1.4859) -> (33.8088, 69.5899, -1.4859)
  line L2741 (33.8088, 69.5899, -1.4859) -> (33.8979, 69.4151, -1.4859)
  line L2742 (33.8979, 69.4151, -1.4859) -> (33.9585, 69.2285, -1.4859)
  line L2743 (33.9585, 69.2285, -1.4859) -> (33.9892, 69.0348, -1.4859)
  line L2744 (33.9892, 69.0348, -1.4859) -> (33.993, 68.9367, -1.4859)
  line L2745 (33.993, 68.9367, -1.4859) -> (33.993, 68.4367, -1.4859)
  line L2746 (33.993, 68.4367, -1.4859) -> (33.9892, 68.3387, -1.4859)
  line L2747 (33.9892, 68.3387, -1.4859) -> (33.9585, 68.1449, -1.4859)
  line L2748 (33.9585, 68.1449, -1.4859) -> (33.8979, 67.9584, -1.4859)
  line L2749 (33.8979, 67.9584, -1.4859) -> (33.8088, 67.7836, -1.4859)
  line L2750 (33.8088, 67.7836, -1.4859) -> (33.6936, 67.6249, -1.4859)
  line L2751 (33.6936, 67.6249, -1.4859) -> (33.5549, 67.4862, -1.4859)
  line L2752 (33.5549, 67.4862, -1.4859) -> (33.3962, 67.3709, -1.4859)
  line L2753 (33.3962, 67.3709, -1.4859) -> (33.2214, 67.2819, -1.4859)
  line L2754 (33.2214, 67.2819, -1.4859) -> (33.0348, 67.2213, -1.4859)
  line L2755 (33.0348, 67.2213, -1.4859) -> (32.8411, 67.1906, -1.4859)
  line L2756 (32.8411, 67.1906, -1.4859) -> (32.645, 67.1906, -1.4859)
  line L2757 (32.645, 67.1906, -1.4859) -> (32.4512, 67.2213, -1.4859)
  line L2758 (32.4512, 67.2213, -1.4859) -> (32.2647, 67.2819, -1.4859)
  line L2759 (32.2647, 67.2819, -1.4859) -> (32.0899, 67.3709, -1.4859)
  line L2760 (32.0899, 67.3709, -1.4859) -> (31.9312, 67.4862, -1.4859)
  line L2761 (31.9312, 67.4862, -1.4859) -> (31.7925, 67.6249, -1.4859)
  line L2762 (31.7925, 67.6249, -1.4859) -> (31.6772, 67.7836, -1.4859)
  line L2763 (31.6772, 67.7836, -1.4859) -> (31.5882, 67.9584, -1.4859)
  line L2764 (31.5882, 67.9584, -1.4859) -> (31.5276, 68.1449, -1.4859)
  line L2765 (31.5276, 68.1449, -1.4859) -> (31.4969, 68.3387, -1.4859)
  line L2766 (31.4969, 68.3387, -1.4859) -> (31.493, 68.4367, -1.4859)
  line L2767 (31.493, 68.4367, -1.4859) -> (31.493, 68.9367, -1.4859)
  line L2768 (31.493, 68.9367, -1.4859) -> (31.4969, 69.0348, -1.4859)
  line L2769 (31.4969, 69.0348, -1.4859) -> (31.5276, 69.2285, -1.4859)
  line L2770 (31.5276, 69.2285, -1.4859) -> (31.5882, 69.4151, -1.4859)
  line L2771 (31.5882, 69.4151, -1.4859) -> (31.6772, 69.5899, -1.4859)
  line L2772 (31.6772, 69.5899, -1.4859) -> (31.7925, 69.7485, -1.4859)
  line L2773 (31.7925, 69.7485, -1.4859) -> (31.9312, 69.8872, -1.4859)
  line L2774 (31.9312, 69.8872, -1.4859) -> (32.0899, 70.0025, -1.4859)
  line L2775 (32.0899, 70.0025, -1.4859) -> (32.2647, 70.0916, -1.4859)
  line L2776 (32.2647, 70.0916, -1.4859) -> (32.4512, 70.1522, -1.4859)
  line L2777 (32.4512, 70.1522, -1.4859) -> (32.645, 70.1829, -1.4859)
  line L2778 (32.645, 70.1829, -1.4859) -> (32.8411, 70.1829, -1.4859)
  line L2779 (32.8411, 70.1829, -1.4859) -> (33.0348, 70.1522, -1.4859)
  line L2780 (67.9598, 70.1522, -1.4859) -> (68.1464, 70.0916, -1.4859)
  line L2781 (68.1464, 70.0916, -1.4859) -> (68.3212, 70.0025, -1.4859)
  line L2782 (68.3212, 70.0025, -1.4859) -> (68.4799, 69.8872, -1.4859)
  line L2783 (68.4799, 69.8872, -1.4859) -> (68.6185, 69.7485, -1.4859)
  line L2784 (68.6185, 69.7485, -1.4859) -> (68.7338, 69.5899, -1.4859)
  line L2785 (68.7338, 69.5899, -1.4859) -> (68.8229, 69.4151, -1.4859)
  line L2786 (68.8229, 69.4151, -1.4859) -> (68.8835, 69.2285, -1.4859)
  line L2787 (68.8835, 69.2285, -1.4859) -> (68.9142, 69.0348, -1.4859)
  line L2788 (68.9142, 69.0348, -1.4859) -> (68.918, 68.9367, -1.4859)
  line L2789 (68.918, 68.9367, -1.4859) -> (68.918, 68.4367, -1.4859)
  line L2790 (68.918, 68.4367, -1.4859) -> (68.9142, 68.3387, -1.4859)
  line L2791 (68.9142, 68.3387, -1.4859) -> (68.8835, 68.1449, -1.4859)
  line L2792 (68.8835, 68.1449, -1.4859) -> (68.8229, 67.9584, -1.4859)
  line L2793 (68.8229, 67.9584, -1.4859) -> (68.7338, 67.7836, -1.4859)
  line L2794 (68.7338, 67.7836, -1.4859) -> (68.6185, 67.6249, -1.4859)
  line L2795 (68.6185, 67.6249, -1.4859) -> (68.4799, 67.4862, -1.4859)
  line L2796 (68.4799, 67.4862, -1.4859) -> (68.3212, 67.3709, -1.4859)
  line L2797 (68.3212, 67.3709, -1.4859) -> (68.1464, 67.2819, -1.4859)
  line L2798 (68.1464, 67.2819, -1.4859) -> (67.9598, 67.2213, -1.4859)
  line L2799 (67.9598, 67.2213, -1.4859) -> (67.7661, 67.1906, -1.4859)
  line L2800 (67.7661, 67.1906, -1.4859) -> (67.57, 67.1906, -1.4859)
  line L2801 (67.57, 67.1906, -1.4859) -> (67.3762, 67.2213, -1.4859)
  line L2802 (67.3762, 67.2213, -1.4859) -> (67.1897, 67.2819, -1.4859)
  line L2803 (67.1897, 67.2819, -1.4859) -> (67.0149, 67.3709, -1.4859)
  line L2804 (67.0149, 67.3709, -1.4859) -> (66.8562, 67.4862, -1.4859)
  line L2805 (66.8562, 67.4862, -1.4859) -> (66.7175, 67.6249, -1.4859)
  line L2806 (66.7175, 67.6249, -1.4859) -> (66.6022, 67.7836, -1.4859)
  line L2807 (66.6022, 67.7836, -1.4859) -> (66.5132, 67.9584, -1.4859)
  line L2808 (66.5132, 67.9584, -1.4859) -> (66.4526, 68.1449, -1.4859)
  line L2809 (66.4526, 68.1449, -1.4859) -> (66.4219, 68.3387, -1.4859)
  line L2810 (66.4219, 68.3387, -1.4859) -> (66.418, 68.4367, -1.4859)
  line L2811 (66.418, 68.4367, -1.4859) -> (66.418, 68.9367, -1.4859)
  line L2812 (66.418, 68.9367, -1.4859) -> (66.4219, 69.0348, -1.4859)
  line L2813 (66.4219, 69.0348, -1.4859) -> (66.4526, 69.2285, -1.4859)
  line L2814 (66.4526, 69.2285, -1.4859) -> (66.5132, 69.4151, -1.4859)
  line L2815 (66.5132, 69.4151, -1.4859) -> (66.6022, 69.5899, -1.4859)
  line L2816 (66.6022, 69.5899, -1.4859) -> (66.7175, 69.7485, -1.4859)
  line L2817 (66.7175, 69.7485, -1.4859) -> (66.8562, 69.8872, -1.4859)
  line L2818 (66.8562, 69.8872, -1.4859) -> (67.0149, 70.0025, -1.4859)
  line L2819 (67.0149, 70.0025, -1.4859) -> (67.1897, 70.0916, -1.4859)
  line L2820 (67.1897, 70.0916, -1.4859) -> (67.3762, 70.1522, -1.4859)
  line L2821 (67.3762, 70.1522, -1.4859) -> (67.57, 70.1829, -1.4859)
  line L2822 (67.57, 70.1829, -1.4859) -> (67.7661, 70.1829, -1.4859)
  line L2823 (67.7661, 70.1829, -1.4859) -> (67.9599, 70.1522, -1.4859)
  line L2824 (102.8849, 70.1522, -1.4859) -> (103.0714, 70.0916, -1.4859)
  line L2825 (103.0714, 70.0916, -1.4859) -> (103.2462, 70.0025, -1.4859)
  line L2826 (103.2462, 70.0025, -1.4859) -> (103.4049, 69.8872, -1.4859)
  line L2827 (103.4049, 69.8872, -1.4859) -> (103.5436, 69.7485, -1.4859)
  line L2828 (103.5436, 69.7485, -1.4859) -> (103.6588, 69.5899, -1.4859)
  line L2829 (103.6588, 69.5899, -1.4859) -> (103.7479, 69.4151, -1.4859)
  line L2830 (103.7479, 69.4151, -1.4859) -> (103.8085, 69.2285, -1.4859)
  line L2831 (103.8085, 69.2285, -1.4859) -> (103.8392, 69.0348, -1.4859)
  line L2832 (103.8392, 69.0348, -1.4859) -> (103.843, 68.9367, -1.4859)
  line L2833 (103.843, 68.9367, -1.4859) -> (103.843, 68.4367, -1.4859)
  line L2834 (103.843, 68.4367, -1.4859) -> (103.8392, 68.3387, -1.4859)
  line L2835 (103.8392, 68.3387, -1.4859) -> (103.8085, 68.1449, -1.4859)
  line L2836 (103.8085, 68.1449, -1.4859) -> (103.7479, 67.9584, -1.4859)
  line L2837 (103.7479, 67.9584, -1.4859) -> (103.6588, 67.7836, -1.4859)
  line L2838 (103.6588, 67.7836, -1.4859) -> (103.5436, 67.6249, -1.4859)
  line L2839 (103.5436, 67.6249, -1.4859) -> (103.4049, 67.4862, -1.4859)
  line L2840 (103.4049, 67.4862, -1.4859) -> (103.2462, 67.3709, -1.4859)
  line L2841 (103.2462, 67.3709, -1.4859) -> (103.0714, 67.2819, -1.4859)
  line L2842 (103.0714, 67.2819, -1.4859) -> (102.8848, 67.2213, -1.4859)
  line L2843 (102.8849, 67.2213, -1.4859) -> (102.6911, 67.1906, -1.4859)
  line L2844 (102.6911, 67.1906, -1.4859) -> (102.495, 67.1906, -1.4859)
  line L2845 (102.495, 67.1906, -1.4859) -> (102.3012, 67.2213, -1.4859)
  line L2846 (102.3012, 67.2213, -1.4859) -> (102.1147, 67.2819, -1.4859)
  line L2847 (102.1147, 67.2819, -1.4859) -> (101.9399, 67.3709, -1.4859)
  line L2848 (101.9399, 67.3709, -1.4859) -> (101.7812, 67.4862, -1.4859)
  line L2849 (101.7812, 67.4862, -1.4859) -> (101.6425, 67.6249, -1.4859)
  line L2850 (101.6425, 67.6249, -1.4859) -> (101.5272, 67.7836, -1.4859)
  line L2851 (101.5272, 67.7836, -1.4859) -> (101.4382, 67.9584, -1.4859)
  line L2852 (101.4382, 67.9584, -1.4859) -> (101.3776, 68.1449, -1.4859)
  line L2853 (101.3776, 68.1449, -1.4859) -> (101.3469, 68.3387, -1.4859)
  line L2854 (101.3469, 68.3387, -1.4859) -> (101.343, 68.4367, -1.4859)
  line L2855 (101.343, 68.4367, -1.4859) -> (101.343, 68.9367, -1.4859)
  line L2856 (101.343, 68.9367, -1.4859) -> (101.3469, 69.0348, -1.4859)
  line L2857 (101.3469, 69.0348, -1.4859) -> (101.3776, 69.2285, -1.4859)
  line L2858 (101.3776, 69.2285, -1.4859) -> (101.4382, 69.4151, -1.4859)
  line L2859 (101.4382, 69.4151, -1.4859) -> (101.5272, 69.5899, -1.4859)
  line L2860 (101.5272, 69.5899, -1.4859) -> (101.6425, 69.7485, -1.4859)
  line L2861 (101.6425, 69.7485, -1.4859) -> (101.7812, 69.8872, -1.4859)
  line L2862 (101.7812, 69.8872, -1.4859) -> (101.9399, 70.0025, -1.4859)
  line L2863 (101.9399, 70.0025, -1.4859) -> (102.1147, 70.0916, -1.4859)
  line L2864 (102.1147, 70.0916, -1.4859) -> (102.3012, 70.1522, -1.4859)
  line L2865 (102.3012, 70.1522, -1.4859) -> (102.495, 70.1829, -1.4859)
  line L2866 (102.495, 70.1829, -1.4859) -> (102.6911, 70.1829, -1.4859)
  line L2867 (102.6911, 70.1829, -1.4859) -> (102.8848, 70.1522, -1.4859)
  line L2868 (137.8098, 70.1522, -1.4859) -> (137.9964, 70.0916, -1.4859)
  line L2869 (137.9964, 70.0916, -1.4859) -> (138.1712, 70.0025, -1.4859)
  line L2870 (138.1712, 70.0025, -1.4859) -> (138.3299, 69.8872, -1.4859)
  line L2871 (138.3299, 69.8872, -1.4859) -> (138.4685, 69.7485, -1.4859)
  line L2872 (138.4685, 69.7485, -1.4859) -> (138.5838, 69.5899, -1.4859)
  line L2873 (138.5838, 69.5899, -1.4859) -> (138.6729, 69.4151, -1.4859)
  line L2874 (138.6729, 69.4151, -1.4859) -> (138.7335, 69.2285, -1.4859)
  line L2875 (138.7335, 69.2285, -1.4859) -> (138.7642, 69.0348, -1.4859)
  line L2876 (138.7642, 69.0348, -1.4859) -> (138.768, 68.9367, -1.4859)
  line L2877 (138.768, 68.9367, -1.4859) -> (138.768, 68.4367, -1.4859)
  line L2878 (138.768, 68.4367, -1.4859) -> (138.7642, 68.3387, -1.4859)
  line L2879 (138.7642, 68.3387, -1.4859) -> (138.7335, 68.1449, -1.4859)
  line L2880 (138.7335, 68.1449, -1.4859) -> (138.6729, 67.9584, -1.4859)
  line L2881 (138.6729, 67.9584, -1.4859) -> (138.5838, 67.7836, -1.4859)
  line L2882 (138.5838, 67.7836, -1.4859) -> (138.4685, 67.6249, -1.4859)
  line L2883 (138.4685, 67.6249, -1.4859) -> (138.3299, 67.4862, -1.4859)
  line L2884 (138.3299, 67.4862, -1.4859) -> (138.1712, 67.3709, -1.4859)
  line L2885 (138.1712, 67.3709, -1.4859) -> (137.9964, 67.2819, -1.4859)
  line L2886 (137.9964, 67.2819, -1.4859) -> (137.8099, 67.2213, -1.4859)
  line L2887 (137.8099, 67.2213, -1.4859) -> (137.6161, 67.1906, -1.4859)
  line L2888 (137.6161, 67.1906, -1.4859) -> (137.42, 67.1906, -1.4859)
  line L2889 (137.42, 67.1906, -1.4859) -> (137.2262, 67.2213, -1.4859)
  line L2890 (137.2262, 67.2213, -1.4859) -> (137.0397, 67.2819, -1.4859)
  line L2891 (137.0397, 67.2819, -1.4859) -> (136.8649, 67.3709, -1.4859)
  line L2892 (136.8649, 67.3709, -1.4859) -> (136.7062, 67.4862, -1.4859)
  line L2893 (136.7062, 67.4862, -1.4859) -> (136.5675, 67.6249, -1.4859)
  line L2894 (136.5675, 67.6249, -1.4859) -> (136.4522, 67.7836, -1.4859)
  line L2895 (136.4522, 67.7836, -1.4859) -> (136.3632, 67.9584, -1.4859)
  line L2896 (136.3632, 67.9584, -1.4859) -> (136.3026, 68.1449, -1.4859)
  line L2897 (136.3026, 68.1449, -1.4859) -> (136.2719, 68.3387, -1.4859)
  line L2898 (136.2719, 68.3387, -1.4859) -> (136.268, 68.4367, -1.4859)
  line L2899 (136.268, 68.4367, -1.4859) -> (136.268, 68.9367, -1.4859)
  line L2900 (136.268, 68.9367, -1.4859) -> (136.2719, 69.0348, -1.4859)
  line L2901 (136.2719, 69.0348, -1.4859) -> (136.3026, 69.2285, -1.4859)
  line L2902 (136.3026, 69.2285, -1.4859) -> (136.3632, 69.4151, -1.4859)
  line L2903 (136.3632, 69.4151, -1.4859) -> (136.4522, 69.5899, -1.4859)
  line L2904 (136.4522, 69.5899, -1.4859) -> (136.5675, 69.7485, -1.4859)
  line L2905 (136.5675, 69.7485, -1.4859) -> (136.7062, 69.8872, -1.4859)
  line L2906 (136.7062, 69.8872, -1.4859) -> (136.8649, 70.0025, -1.4859)
  line L2907 (136.8649, 70.0025, -1.4859) -> (137.0397, 70.0916, -1.4859)
  line L2908 (137.0397, 70.0916, -1.4859) -> (137.2262, 70.1522, -1.4859)
  line L2909 (137.2262, 70.1522, -1.4859) -> (137.42, 70.1829, -1.4859)
  line L2910 (137.42, 70.1829, -1.4859) -> (137.6161, 70.1829, -1.4859)
  line L2911 (137.6161, 70.1829, -1.4859) -> (137.8099, 70.1522, -1.4859)
  line L2912 (24.9666, 73.2153, -1.4859) -> (22.9666, 73.2153, -1.4859)
  line L2913 (22.9666, 73.2153, -1.4859) -> (22.9666, 76.4153, -1.4859)
  line L2914 (22.9666, 76.4153, -1.4859) -> (24.9666, 76.4153, -1.4859)
  line L2915 (24.9666, 76.4153, -1.4859) -> (24.9666, 73.2153, -1.4859)
  line L2916 (59.8916, 73.2153, -1.4859) -> (57.8916, 73.2153, -1.4859)
  line L2917 (57.8916, 73.2153, -1.4859) -> (57.8916, 76.4153, -1.4859)
  line L2918 (57.8916, 76.4153, -1.4859) -> (59.8916, 76.4153, -1.4859)
  line L2919 (59.8916, 76.4153, -1.4859) -> (59.8916, 73.2153, -1.4859)
  line L2920 (94.8166, 73.2153, -1.4859) -> (92.8166, 73.2153, -1.4859)
  line L2921 (92.8166, 73.2153, -1.4859) -> (92.8166, 76.4153, -1.4859)
  line L2922 (92.8166, 76.4153, -1.4859) -> (94.8166, 76.4153, -1.4859)
  line L2923 (94.8166, 76.4153, -1.4859) -> (94.8166, 73.2153, -1.4859)
  line L2924 (129.7416, 73.2153, -1.4859) -> (127.7416, 73.2153, -1.4859)
  line L2925 (127.7416, 73.2153, -1.4859) -> (127.7416, 76.4153, -1.4859)
  line L2926 (127.7416, 76.4153, -1.4859) -> (129.7416, 76.4153, -1.4859)
  line L2927 (129.7416, 76.4153, -1.4859) -> (129.7416, 73.2153, -1.4859)
  line L2928 (27.0269, 76.3722, -1.4859) -> (27.208, 76.2972, -1.4859)
  line L2929 (27.208, 76.2972, -1.4859) -> (27.371, 76.1883, -1.4859)
  line L2930 (27.371, 76.1883, -1.4859) -> (27.5096, 76.0497, -1.4859)
  line L2931 (27.5096, 76.0497, -1.4859) -> (27.6185, 75.8867, -1.4859)
  line L2932 (27.6185, 75.8867, -1.4859) -> (27.6935, 75.7056, -1.4859)
  line L2933 (27.6935, 75.7056, -1.4859) -> (27.7318, 75.5133, -1.4859)
  line L2934 (27.7318, 75.5133, -1.4859) -> (27.7366, 75.4153, -1.4859)
  line L2935 (27.7366, 75.4153, -1.4859) -> (27.7366, 74.2153, -1.4859)
  line L2936 (27.7366, 74.2153, -1.4859) -> (27.7318, 74.1173, -1.4859)
  line L2937 (27.7318, 74.1173, -1.4859) -> (27.6935, 73.925, -1.4859)
  line L2938 (27.6935, 73.925, -1.4859) -> (27.6185, 73.7439, -1.4859)
  line L2939 (27.6185, 73.7439, -1.4859) -> (27.5096, 73.5809, -1.4859)
  line L2940 (27.5096, 73.5809, -1.4859) -> (27.371, 73.4423, -1.4859)
  line L2941 (27.371, 73.4423, -1.4859) -> (27.208, 73.3334, -1.4859)
  line L2942 (27.208, 73.3334, -1.4859) -> (27.0269, 73.2583, -1.4859)
  line L2943 (27.0269, 73.2583, -1.4859) -> (26.8346, 73.2201, -1.4859)
  line L2944 (26.8346, 73.2201, -1.4859) -> (26.6386, 73.2201, -1.4859)
  line L2945 (26.6386, 73.2201, -1.4859) -> (26.4463, 73.2583, -1.4859)
  line L2946 (26.4463, 73.2583, -1.4859) -> (26.2652, 73.3334, -1.4859)
  line L2947 (26.2652, 73.3334, -1.4859) -> (26.1022, 73.4423, -1.4859)
  line L2948 (26.1022, 73.4423, -1.4859) -> (25.9636, 73.5809, -1.4859)
  line L2949 (25.9636, 73.5809, -1.4859) -> (25.8547, 73.7439, -1.4859)
  line L2950 (25.8547, 73.7439, -1.4859) -> (25.7797, 73.925, -1.4859)
  line L2951 (25.7797, 73.925, -1.4859) -> (25.7414, 74.1173, -1.4859)
  line L2952 (25.7414, 74.1173, -1.4859) -> (25.7366, 74.2153, -1.4859)
  line L2953 (25.7366, 74.2153, -1.4859) -> (25.7366, 75.4153, -1.4859)
  line L2954 (25.7366, 75.4153, -1.4859) -> (25.7414, 75.5133, -1.4859)
  line L2955 (25.7414, 75.5133, -1.4859) -> (25.7797, 75.7056, -1.4859)
  line L2956 (25.7797, 75.7056, -1.4859) -> (25.8547, 75.8867, -1.4859)
  line L2957 (25.8547, 75.8867, -1.4859) -> (25.9636, 76.0497, -1.4859)
  line L2958 (25.9636, 76.0497, -1.4859) -> (26.1022, 76.1883, -1.4859)
  line L2959 (26.1022, 76.1883, -1.4859) -> (26.2652, 76.2972, -1.4859)
  line L2960 (26.2652, 76.2972, -1.4859) -> (26.4463, 76.3722, -1.4859)
  line L2961 (26.4463, 76.3722, -1.4859) -> (26.6386, 76.4105, -1.4859)
  line L2962 (26.6386, 76.4105, -1.4859) -> (26.8346, 76.4105, -1.4859)
  line L2963 (26.8346, 76.4105, -1.4859) -> (27.0269, 76.3722, -1.4859)
  line L2964 (29.7569, 76.3722, -1.4859) -> (29.938, 76.2972, -1.4859)
  line L2965 (29.938, 76.2972, -1.4859) -> (30.101, 76.1883, -1.4859)
  line L2966 (30.101, 76.1883, -1.4859) -> (30.2396, 76.0497, -1.4859)
  line L2967 (30.2396, 76.0497, -1.4859) -> (30.3485, 75.8867, -1.4859)
  line L2968 (30.3485, 75.8867, -1.4859) -> (30.4235, 75.7056, -1.4859)
  line L2969 (30.4235, 75.7056, -1.4859) -> (30.4618, 75.5133, -1.4859)
  line L2970 (30.4618, 75.5133, -1.4859) -> (30.4666, 75.4153, -1.4859)
  line L2971 (30.4666, 75.4153, -1.4859) -> (30.4666, 74.2153, -1.4859)
  line L2972 (30.4666, 74.2153, -1.4859) -> (30.4618, 74.1173, -1.4859)
  line L2973 (30.4618, 74.1173, -1.4859) -> (30.4235, 73.925, -1.4859)
  line L2974 (30.4235, 73.925, -1.4859) -> (30.3485, 73.7439, -1.4859)
  line L2975 (30.3485, 73.7439, -1.4859) -> (30.2396, 73.5809, -1.4859)
  line L2976 (30.2396, 73.5809, -1.4859) -> (30.101, 73.4423, -1.4859)
  line L2977 (30.101, 73.4423, -1.4859) -> (29.938, 73.3334, -1.4859)
  line L2978 (29.938, 73.3334, -1.4859) -> (29.7569, 73.2583, -1.4859)
  line L2979 (29.7569, 73.2583, -1.4859) -> (29.5646, 73.2201, -1.4859)
  line L2980 (29.5646, 73.2201, -1.4859) -> (29.3686, 73.2201, -1.4859)
  line L2981 (29.3686, 73.2201, -1.4859) -> (29.1763, 73.2583, -1.4859)
  line L2982 (29.1763, 73.2583, -1.4859) -> (28.9952, 73.3334, -1.4859)
  line L2983 (28.9952, 73.3334, -1.4859) -> (28.8322, 73.4423, -1.4859)
  line L2984 (28.8322, 73.4423, -1.4859) -> (28.6936, 73.5809, -1.4859)
  line L2985 (28.6936, 73.5809, -1.4859) -> (28.5847, 73.7439, -1.4859)
  line L2986 (28.5847, 73.7439, -1.4859) -> (28.5097, 73.925, -1.4859)
  line L2987 (28.5097, 73.925, -1.4859) -> (28.4714, 74.1173, -1.4859)
  line L2988 (28.4714, 74.1173, -1.4859) -> (28.4666, 74.2153, -1.4859)
  line L2989 (28.4666, 74.2153, -1.4859) -> (28.4666, 75.4153, -1.4859)
  line L2990 (28.4666, 75.4153, -1.4859) -> (28.4714, 75.5133, -1.4859)
  line L2991 (28.4714, 75.5133, -1.4859) -> (28.5097, 75.7056, -1.4859)
  line L2992 (28.5097, 75.7056, -1.4859) -> (28.5847, 75.8867, -1.4859)
  line L2993 (28.5847, 75.8867, -1.4859) -> (28.6936, 76.0497, -1.4859)
  line L2994 (28.6936, 76.0497, -1.4859) -> (28.8322, 76.1883, -1.4859)
  line L2995 (28.8322, 76.1883, -1.4859) -> (28.9952, 76.2972, -1.4859)
  line L2996 (28.9952, 76.2972, -1.4859) -> (29.1763, 76.3722, -1.4859)
  line L2997 (29.1763, 76.3722, -1.4859) -> (29.3686, 76.4105, -1.4859)
  line L2998 (29.3686, 76.4105, -1.4859) -> (29.5646, 76.4105, -1.4859)
  line L2999 (29.5646, 76.4105, -1.4859) -> (29.7569, 76.3722, -1.4859)
  line L3000 (61.9519, 76.3722, -1.4859) -> (62.133, 76.2972, -1.4859)
  line L3001 (62.133, 76.2972, -1.4859) -> (62.296, 76.1883, -1.4859)
  line L3002 (62.296, 76.1883, -1.4859) -> (62.4346, 76.0497, -1.4859)
  line L3003 (62.4346, 76.0497, -1.4859) -> (62.5435, 75.8867, -1.4859)
  line L3004 (62.5435, 75.8867, -1.4859) -> (62.6185, 75.7056, -1.4859)
  line L3005 (62.6185, 75.7056, -1.4859) -> (62.6568, 75.5133, -1.4859)
  line L3006 (62.6568, 75.5133, -1.4859) -> (62.6616, 75.4153, -1.4859)
  line L3007 (62.6616, 75.4153, -1.4859) -> (62.6616, 74.2153, -1.4859)
  line L3008 (62.6616, 74.2153, -1.4859) -> (62.6568, 74.1173, -1.4859)
  line L3009 (62.6568, 74.1173, -1.4859) -> (62.6185, 73.925, -1.4859)
  line L3010 (62.6185, 73.925, -1.4859) -> (62.5435, 73.7439, -1.4859)
  line L3011 (62.5435, 73.7439, -1.4859) -> (62.4346, 73.5809, -1.4859)
  line L3012 (62.4346, 73.5809, -1.4859) -> (62.296, 73.4423, -1.4859)
  line L3013 (62.296, 73.4423, -1.4859) -> (62.133, 73.3334, -1.4859)
  line L3014 (62.133, 73.3334, -1.4859) -> (61.9519, 73.2583, -1.4859)
  line L3015 (61.9519, 73.2583, -1.4859) -> (61.7596, 73.2201, -1.4859)
  line L3016 (61.7596, 73.2201, -1.4859) -> (61.5636, 73.2201, -1.4859)
  line L3017 (61.5636, 73.2201, -1.4859) -> (61.3713, 73.2583, -1.4859)
  line L3018 (61.3713, 73.2583, -1.4859) -> (61.1902, 73.3334, -1.4859)
  line L3019 (61.1902, 73.3334, -1.4859) -> (61.0272, 73.4423, -1.4859)
  line L3020 (61.0272, 73.4423, -1.4859) -> (60.8886, 73.5809, -1.4859)
  line L3021 (60.8886, 73.5809, -1.4859) -> (60.7797, 73.7439, -1.4859)
  line L3022 (60.7797, 73.7439, -1.4859) -> (60.7047, 73.925, -1.4859)
  line L3023 (60.7047, 73.925, -1.4859) -> (60.6664, 74.1173, -1.4859)
  line L3024 (60.6664, 74.1173, -1.4859) -> (60.6616, 74.2153, -1.4859)
  line L3025 (60.6616, 74.2153, -1.4859) -> (60.6616, 75.4153, -1.4859)
  line L3026 (60.6616, 75.4153, -1.4859) -> (60.6664, 75.5133, -1.4859)
  line L3027 (60.6664, 75.5133, -1.4859) -> (60.7047, 75.7056, -1.4859)
  line L3028 (60.7047, 75.7056, -1.4859) -> (60.7797, 75.8867, -1.4859)
  line L3029 (60.7797, 75.8867, -1.4859) -> (60.8886, 76.0497, -1.4859)
  line L3030 (60.8886, 76.0497, -1.4859) -> (61.0272, 76.1883, -1.4859)
  line L3031 (61.0272, 76.1883, -1.4859) -> (61.1902, 76.2972, -1.4859)
  line L3032 (61.1902, 76.2972, -1.4859) -> (61.3713, 76.3722, -1.4859)
  line L3033 (61.3713, 76.3722, -1.4859) -> (61.5636, 76.4105, -1.4859)
  line L3034 (61.5636, 76.4105, -1.4859) -> (61.7596, 76.4105, -1.4859)
  line L3035 (61.7596, 76.4105, -1.4859) -> (61.9519, 76.3722, -1.4859)
  line L3036 (64.6819, 76.3722, -1.4859) -> (64.863, 76.2972, -1.4859)
  line L3037 (64.863, 76.2972, -1.4859) -> (65.026, 76.1883, -1.4859)
  line L3038 (65.026, 76.1883, -1.4859) -> (65.1646, 76.0497, -1.4859)
  line L3039 (65.1646, 76.0497, -1.4859) -> (65.2735, 75.8867, -1.4859)
  line L3040 (65.2735, 75.8867, -1.4859) -> (65.3485, 75.7056, -1.4859)
  line L3041 (65.3485, 75.7056, -1.4859) -> (65.3868, 75.5133, -1.4859)
  line L3042 (65.3868, 75.5133, -1.4859) -> (65.3916, 75.4153, -1.4859)
  line L3043 (65.3916, 75.4153, -1.4859) -> (65.3916, 74.2153, -1.4859)
  line L3044 (65.3916, 74.2153, -1.4859) -> (65.3868, 74.1173, -1.4859)
  line L3045 (65.3868, 74.1173, -1.4859) -> (65.3485, 73.925, -1.4859)
  line L3046 (65.3485, 73.925, -1.4859) -> (65.2735, 73.7439, -1.4859)
  line L3047 (65.2735, 73.7439, -1.4859) -> (65.1646, 73.5809, -1.4859)
  line L3048 (65.1646, 73.5809, -1.4859) -> (65.026, 73.4423, -1.4859)
  line L3049 (65.026, 73.4423, -1.4859) -> (64.863, 73.3334, -1.4859)
  line L3050 (64.863, 73.3334, -1.4859) -> (64.6819, 73.2583, -1.4859)
  line L3051 (64.6819, 73.2583, -1.4859) -> (64.4896, 73.2201, -1.4859)
  line L3052 (64.4896, 73.2201, -1.4859) -> (64.2936, 73.2201, -1.4859)
  line L3053 (64.2936, 73.2201, -1.4859) -> (64.1013, 73.2583, -1.4859)
  line L3054 (64.1013, 73.2583, -1.4859) -> (63.9202, 73.3334, -1.4859)
  line L3055 (63.9202, 73.3334, -1.4859) -> (63.7572, 73.4423, -1.4859)
  line L3056 (63.7572, 73.4423, -1.4859) -> (63.6186, 73.5809, -1.4859)
  line L3057 (63.6186, 73.5809, -1.4859) -> (63.5097, 73.7439, -1.4859)
  line L3058 (63.5097, 73.7439, -1.4859) -> (63.4347, 73.925, -1.4859)
  line L3059 (63.4347, 73.925, -1.4859) -> (63.3964, 74.1173, -1.4859)
  line L3060 (63.3964, 74.1173, -1.4859) -> (63.3916, 74.2153, -1.4859)
  line L3061 (63.3916, 74.2153, -1.4859) -> (63.3916, 75.4153, -1.4859)
  line L3062 (63.3916, 75.4153, -1.4859) -> (63.3964, 75.5133, -1.4859)
  line L3063 (63.3964, 75.5133, -1.4859) -> (63.4347, 75.7056, -1.4859)